f3d-09857774cc2c (Autodesk Fusion 360 design; units mm, degrees)
Autodesk Fusion 360 part; units mm, degrees
sketch "Sketch3" plane through (0, 0, 0) normal (0, 0, 1) x (1, 0, 0)
  line L0 (0, 0) -> (600, 0)
  line L1 (600, 0) -> (600, 975)
  line L2 (0, 1193.3821) -> (0, 0)
  line L3 (0, 1193.3821) -> (600, 975)
  line L4 (600, 0) -> (584, 0)
  line L5 (584, 0) -> (584, 975)
  line L6 (584, 975) -> (600, 975)
  line L7 (600, 975) -> (600, 0)
  line L8 (0, 1187.5586) -> (16, 1187.5586)
  line L9 (16, 1187.5586) -> (16, 1037.5586)
  line L10 (16, 1037.5586) -> (0, 1037.5586)
  line L11 (0, 1037.5586) -> (0, 1187.5586)
  line L12 (0, 500) -> (16, 500)
  line L13 (16, 500) -> (16, 0)
  line L14 (16, 0) -> (0, 0)
  line L15 (0, 0) -> (0, 500)
  line L16 (0, 500) -> (584, 500)
  line L17 (584, 500) -> (584, 516)
  line L18 (584, 516) -> (0, 516)
  line L19 (0, 516) -> (0, 500)
  dimension "d1" = 975
  dimension "d2" = 600
  dimension "d5" = 20
  dimension "d6" = 16
  dimension "d7" = 975
  dimension "d8" = 16
  dimension "d9" = 150
  dimension "d10" = 16
  dimension "d11" = 500
  dimension "d12" = 16
  constraint horizontal L0
  constraint vertical L1
  constraint vertical L2
  constraint coincident L0.start L2.end
  constraint coincident L2.start L3.start
  constraint horizontal L4
  constraint vertical L5
  constraint horizontal L6
  constraint vertical L7
  constraint horizontal L8
  constraint vertical L9
  constraint horizontal L10
  constraint vertical L11
  constraint coincident L2 L8.start
  constraint horizontal L12
  constraint vertical L13
  constraint horizontal L14
  constraint vertical L15
  constraint coincident L2 L12.start
  constraint coincident L3 L8.end
  constraint horizontal L16
  constraint vertical L17
  constraint horizontal L18
  constraint vertical L19
  constraint coincident L5 L17.end
  measures "d1" distance of L0.end L1.end
  measures "d2" distance of L0.start L0.end
  measures "d5" angle of L0 L3
  measures "d6" distance of L5 L7
  measures "d7" distance of L4.end L5.end
  measures "d8" distance of L9 L11
  measures "d9" distance of L8.end L9.end
  measures "d10" distance of L13 L15
  measures "d11" distance of L12.end L13.end
  measures "d12" distance of L16 L18
extrude "Extrude1" add sketch "Sketch3" against normal blind 16 makes body 1 in component "Component'"
extrude "Extrude1'" add sketch "Sketch3" along normal blind 718 separate body contours L2 L8 L9 L10 L11 makes body 2 in component "Component''"
extrude "Extrude1''" add sketch "Sketch3" along normal blind 718 separate body contours L0 L1 L4 L5 L6 L7 L17 makes body 3 in component "Component'''"
extrude "Extrude1'''" add sketch "Sketch3" along normal blind 718 separate body contours L2 L5 L12 L16 L17 L18 L19 makes body 4 in component "Component''''"
extrude "Extrude1''''" add sketch "Sketch3" along normal blind 718 separate body contours L0 L2 L12 L13 L14 L15 L16 makes body 5 in component "Component'''''"
ref_plane "WorkPlane1" through (300, 596.6911, 359) normal (0, 0, 1) x (1, 0, 0)
mirror "Mirror1" about plane through (300, 596.6911, 359) normal (0, 0, 1) of bodies 1 makes body 6 in component "Component'"
ref_plane "WorkPlane2" through (300, 1084.1911, 726) normal (0.34202, 0.939693, 0) x (0.939693, -0.34202, 0)
sketch "Sketch4" plane through (383.5456, 1053.7829, 0) normal (0.34202, 0.939693, 0) x (0.939693, -0.34202, 0)
  line L0 (-408.1607, 0) -> (230.3459, 0) construction
  line L1 (230.3459, 0) -> (230.3459, 16) construction
  line L2 (230.3459, 16) -> (-408.1607, 16) construction
  line L3 (-408.1607, 16) -> (-408.1607, 0) construction
  line L4 (230.3459, 0) -> (215.3109, 0) construction
  line L5 (215.3109, 0) -> (215.3109, -718) construction
  line L6 (215.3109, -718) -> (230.3459, -718) construction
  line L7 (230.3459, -718) -> (230.3459, 0) construction
  line L8 (-391.1339, 0) -> (-406.169, 0) construction
  line L9 (-406.169, 0) -> (-406.169, -718) construction
  line L10 (-406.169, -718) -> (-391.1339, -718) construction
  line L11 (-391.1339, -718) -> (-391.1339, 0) construction
  line L12 (230.3459, -718) -> (-408.1607, -718) construction
  line L13 (-408.1607, -718) -> (-408.1607, -734) construction
  line L14 (-408.1607, -734) -> (230.3459, -734) construction
  line L15 (230.3459, -734) -> (230.3459, -718) construction
  line L16 (-408.1607, 16) -> (230.3459, -734) construction
  line L17 (330.9426, 294.8) -> (-508.7574, 294.8)
  line L18 (-508.7574, 294.8) -> (-508.7574, -1012.8)
  line L19 (-508.7574, -1012.8) -> (330.9426, -1012.8)
  line L20 (330.9426, -1012.8) -> (330.9426, 294.8)
  line L21 (330.9426, 294.8) -> (-508.7574, -1012.8) construction
  line L22 (-508.7574, 294.8) -> (330.9426, -1012.8) construction
  line L23 (-508.7574, 294.8) -> (330.9426, 294.8)
  line L24 (330.9426, 294.8) -> (330.9426, 278.8)
  line L25 (330.9426, 278.8) -> (-508.7574, 278.8)
  line L26 (-508.7574, 278.8) -> (-508.7574, 294.8)
  line L27 (-508.7574, -1012.8) -> (330.9426, -1012.8)
  line L28 (330.9426, -1012.8) -> (330.9426, -996.8)
  line L29 (330.9426, -996.8) -> (-508.7574, -996.8)
  line L30 (-508.7574, -996.8) -> (-508.7574, -1012.8)
  line L31 (-508.7574, 278.8) -> (-492.7574, 278.8)
  line L32 (-492.7574, 278.8) -> (-492.7574, -996.8)
  line L33 (-492.7574, -996.8) -> (-508.7574, -996.8)
  line L34 (-508.7574, -996.8) -> (-508.7574, 278.8)
  line L35 (330.9426, 278.8) -> (314.9426, 278.8)
  line L36 (314.9426, 278.8) -> (314.9426, -996.8)
  line L37 (314.9426, -996.8) -> (330.9426, -996.8)
  line L38 (330.9426, -996.8) -> (330.9426, 278.8)
  line L39 (-88.9074, -359) -> (-88.9074, -996.8) construction
  line L40 (-88.9074, -359) -> (-88.9074, 278.8) construction
  point P0 (-88.9074, -359)
  point P1 (-88.9074, -359)
  point P2 (-88.9074, -511.8)
  point P3 (-88.9074, -206.2)
  dimension "d26" = 839.7
  dimension "d27" = 1307.6
  dimension "d28" = 16
  dimension "d29" = 16
  dimension "d30" = 16
  dimension "d31" = 16
  dimension "d38" = 485
  dimension "d39" = 485
  constraint coincident L2.end L3.start
  constraint coincident L14.end L15.start
  constraint midpoint L16 P1
  constraint horizontal L17
  constraint perpendicular L17 L18
  constraint parallel L17 L19
  constraint parallel L18 L20
  constraint coincident L21 P1
  constraint coincident L22 P1
  constraint coincident P1 P0
  constraint horizontal L23
  constraint vertical L24
  constraint horizontal L25
  constraint vertical L26
  constraint coincident L20 L24.end
  constraint horizontal L27
  constraint vertical L28
  constraint horizontal L29
  constraint vertical L30
  constraint coincident L20 L28.end
  constraint horizontal L31
  constraint vertical L32
  constraint horizontal L33
  constraint vertical L34
  constraint coincident L29 L32.end
  constraint horizontal L35
  constraint vertical L36
  constraint horizontal L37
  constraint vertical L38
  constraint coincident L29 L36.end
  constraint midpoint L29 L39.end
  constraint midpoint L25 L40.end
  constraint coincident L39 P2
  constraint coincident L40 P3
  measures "d26" distance of L17.start L17.end
  measures "d27" distance of L17.end L18.end
  measures "d28" distance of L19 L29
  measures "d29" distance of L17 L25
  measures "d30" distance of L18 L32
  measures "d31" distance of L36 L38
  measures "d38" distance of L29 P2
  measures "d39" distance of L25 P3
extrude "Extrude1'''''" add sketch "Sketch4" along normal blind 104.5 separate body contours L20 L25 L29 L35 L36 L37 L38 | L18 L25 L29 L31 L32 L33 L34 makes body 7 at (-82.6162, 1260.5209, 146.4) makes body 8 at (718.3574, 1006.0592, 571.6) in component "Component''''''"
extrude "Extrude1''''''" add sketch "Sketch4" along normal blind 104.5 separate body contours L17 L18 L20 L23 L24 L25 L26 L31 L35 | L18 L19 L20 L27 L28 L29 L30 L33 L37 makes body 9 at (443.4237, 1069.058, 996.8) makes body 10 at (455.3374, 1101.7906, -278.8) in component "Component'''''''"
extrude "Extrude1'''''''" add sketch "Sketch4" along normal blind 16 separate body contours L25 L29 L32 L36 makes body 11 in component "Component''''''''"
sketch "Sketch5" plane through (389.0179, 1068.818, 0) normal (0.34202, 0.939693, 0) x (0, 0, -1)
  line L0 (278.8, 492.7574) -> (-996.8, 492.7574)
  line L1 (-996.8, 492.7574) -> (-996.8, -314.9426)
  line L2 (-996.8, -314.9426) -> (278.8, -314.9426)
  line L3 (278.8, -314.9426) -> (278.8, 492.7574)
  point P0 (-511.8, 88.9074)
  point P1 (-206.2, 88.9074)
hole "Hole1" at (305.4723, 1099.2262, 511.8) at (305.4723, 1099.2262, 206.2) direction (-0.34202, -0.939693, 0) diameter 100 depth 16 tip angle 180 bodies 11 in component "Component''''''''"
extrude "Extrude1''''''''" add sketch "Sketch4" against normal blind 78.5 from surface at 104.5 separate body contours L25 L29 L32 L36 makes body 12 in component "Component'''''''''"
sketch "Sketch6" plane through (0, 0, 1012.8) normal (0, 0, 1) x (1, 0, 0)
  line L0 (-94.5299, 1227.7882) -> (694.5299, 940.5939)
  line L1 (694.5299, 940.5939) -> (730.2711, 1038.7918)
  line L2 (730.2711, 1038.7918) -> (-58.7888, 1325.9861)
  line L3 (-58.7888, 1325.9861) -> (-94.5299, 1227.7882)
  dimension "d46" = 824.801
  measures "d46" horizontal distance of L0.start L1.end
move_face "Габарит BOE — зазор 2 мм по каждой стороне" offset -2 4 faces at (191.3438, 1179.2533, 996.8) (697.3369, 995.0869, 146.4) (191.3438, 1179.2533, -278.8) (-61.6528, 1271.3365, 146.4) on bodies 12 in component "Component'''''''''"
ref_plane "WorkPlane1" through (0, 0, -88.5) normal (0, 0, 1) x (1, 0, 0) in component "Component''''''''''"
sketch "Sketch1" plane through (0, 0, -88.5) normal (0, 0, 1) x (1, 0, 0) in component "Component''''''''''"
  line L0 (-225, -173.65) -> (-175, -173.65)
  line L1 (-175, -173.65) -> (-175, -157.65)
  line L2 (-175, -157.65) -> (-225, -157.65)
  line L3 (-225, -157.65) -> (-225, -173.65)
extrude "ОП-1 — опирание 10 мм" add sketch "Sketch1" along normal blind 10 separate body makes body 13 in component "Component''''''''''"
sketch "Sketch2" plane through (0, 0, -88.5) normal (0, 0, 1) x (1, 0, 0) in component "Component''''''''''"
  line L0 (175, -173.65) -> (225, -173.65)
  line L1 (225, -173.65) -> (225, -157.65)
  line L2 (225, -157.65) -> (175, -157.65)
  line L3 (175, -157.65) -> (175, -173.65)
extrude "ОП-1 — опирание 10 мм (1)" add sketch "Sketch2" along normal blind 10 separate body makes body 14 in component "Component''''''''''"
sketch "Sketch3 (2)" plane through (0, 0, -88.5) normal (0, 0, 1) x (1, 0, 0) in component "Component''''''''''"
  line L0 (-225, 226.35) -> (-175, 226.35)
  line L1 (-175, 226.35) -> (-175, 242.35)
  line L2 (-175, 242.35) -> (-225, 242.35)
  line L3 (-225, 242.35) -> (-225, 226.35)
extrude "ОП-1 — опирание 10 мм (2)" add sketch "Sketch3 (2)" along normal blind 10 separate body makes body 15 in component "Component''''''''''"
sketch "Sketch4 (2)" plane through (0, 0, -88.5) normal (0, 0, 1) x (1, 0, 0) in component "Component''''''''''"
  line L0 (175, 226.35) -> (225, 226.35)
  line L1 (225, 226.35) -> (225, 242.35)
  line L2 (225, 242.35) -> (175, 242.35)
  line L3 (175, 242.35) -> (175, 226.35)
extrude "ОП-1 — опирание 10 мм (3)" add sketch "Sketch4 (2)" along normal blind 10 separate body makes body 16 in component "Component''''''''''"
sketch "Sketch1 (2)" plane through (0, 0, 0) normal (0, 0, 1) x (1, 0, 0) in component "Component'''''''''''"
  line L0 (653.8, 419.85) -> (-653.8, 419.85)
  line L1 (-653.8, 419.85) -> (-653.8, -419.85)
  line L2 (-653.8, -419.85) -> (653.8, -419.85)
  line L3 (653.8, -419.85) -> (653.8, 419.85)
  line L4 (606, 309.95) -> (-606, 309.95)
  line L5 (-606, 309.95) -> (-606, -372.05)
  line L6 (-606, -372.05) -> (606, -372.05)
  line L7 (606, -372.05) -> (606, 309.95)
  dimension "d67" = 1307.6
  dimension "d68" = 839.7
  dimension "d69" = 1212
  dimension "d70" = 682
  dimension "d73" = 653.8
  dimension "d74" = 419.85
  dimension "d75" = 606
  dimension "d76" = 372.05
  constraint horizontal L0
  constraint vertical L1
  constraint horizontal L2
  constraint vertical L3
  constraint horizontal L4
  constraint vertical L5
  constraint horizontal L6
  constraint vertical L7
  measures "d67" horizontal distance of L1.end L2.end
  measures "d68" vertical distance of L0.start L2.end
  measures "d69" horizontal distance of L5.end L6.end
  measures "d70" vertical distance of L4.start L6.end
  measures "d73" horizontal distance of origin L1.end
  measures "d74" vertical distance of origin L1.end
  measures "d75" horizontal distance of origin L5.end
  measures "d76" vertical distance of origin L5.end
extrude "ПС-1 — полистирол 2 мм" add sketch "Sketch1 (2)" along normal blind 2 separate body makes body 17 in component "Component'''''''''''"
delete_body "RemoveBody1" bodies 12 in component "Component'''''''''"
ref_plane "WorkPlane1" through (0, 0, -24.1) normal (0, 0, 1) x (1, 0, 0) in component "Component''''''''''''"
sketch "Sketch1 (3)" plane through (0, 0, -24.1) normal (0, 0, 1) x (1, 0, 0) in component "Component''''''''''''"
  line L0 (-635.8, -401.85) -> (635.8, -401.85)
  line L1 (635.8, -401.85) -> (635.8, 401.85)
  line L2 (635.8, 401.85) -> (-635.8, 401.85)
  line L3 (-635.8, 401.85) -> (-635.8, -401.85)
extrude "Передняя панель — 24,1 мм (1)" add sketch "Sketch1 (3)" along normal blind 23.1 separate body makes body 18 in component "Component''''''''''''"
ref_plane "WorkPlane2" through (0, 0, -1) normal (0, 0, 1) x (1, 0, 0) in component "Component''''''''''''"
sketch "Sketch2 (2)" plane through (0, 0, -1) normal (0, 0, 1) x (1, 0, 0) in component "Component''''''''''''"
  line L0 (-635.8, -401.85) -> (635.8, -401.85)
  line L1 (635.8, -401.85) -> (635.8, 401.85)
  line L2 (635.8, 401.85) -> (-635.8, 401.85)
  line L3 (-635.8, 401.85) -> (-635.8, -401.85)
  line L4 (-606, -372.05) -> (606, -372.05)
  line L5 (606, -372.05) -> (606, 309.95)
  line L6 (606, 309.95) -> (-606, 309.95)
  line L7 (-606, 309.95) -> (-606, -372.05)
extrude "Передняя рамка — без кнопок (1)" add sketch "Sketch2 (2)" along normal blind 1 bodies 18 in component "Component''''''''''''"
ref_plane "WorkPlane3" through (0, 0, -24.1) normal (0, 0, 1) x (1, 0, 0) in component "Component''''''''''''"
sketch "Sketch3 (3)" plane through (0, 0, -24.1) normal (0, 0, 1) x (1, 0, 0) in component "Component''''''''''''"
  line L0 (-607, -378) -> (607, -378)
  line L1 (607, -378) -> (607, 256)
  line L2 (607, 256) -> (-607, 256)
  line L3 (-607, 256) -> (-607, -378)
extrude "Задний кожух — глубина 43,5 мм (1)" add sketch "Sketch3 (3)" against normal blind 19.4 bodies 18 in component "Component''''''''''''"
ref_plane "WorkPlane4" through (0, 0, -43.5) normal (0, 0, 1) x (1, 0, 0) in component "Component''''''''''''"
sketch "Sketch4 (3)" plane through (0, 0, -43.5) normal (0, 0, 1) x (1, 0, 0) in component "Component''''''''''''"
  line L0 (-548, -119) -> (548, -119)
  line L1 (548, -119) -> (548, 258)
  line L2 (548, 258) -> (225, 258)
  line L3 (225, 258) -> (225, 310)
  line L4 (225, 310) -> (-185, 310)
  line L5 (-185, 310) -> (-185, 258)
  line L6 (-185, 258) -> (-548, 258)
  line L7 (-548, 258) -> (-548, -119)
extrude "Нижний выступ корпуса — глубина 78,5 мм (1)" add sketch "Sketch4 (3)" against normal blind 35 bodies 18 in component "Component''''''''''''"
ref_plane "WorkPlane5" through (0, 0, -43.5) normal (0, 0, 1) x (1, 0, 0) in component "Component''''''''''''"
sketch "Sketch5 (2)" plane through (0, 0, -43.5) normal (0, 0, 1) x (1, 0, 0) in component "Component''''''''''''"
  line L0 (-230, -182) -> (-170, -182)
  line L1 (-170, -182) -> (-170, -145)
  line L2 (-170, -145) -> (-230, -145)
  line L3 (-230, -145) -> (-230, -182)
extrude "Верхний выступ задника -200 (1)" add sketch "Sketch5 (2)" against normal blind 35 bodies 18 in component "Component''''''''''''"
ref_plane "WorkPlane6" through (0, 0, -43.5) normal (0, 0, 1) x (1, 0, 0) in component "Component''''''''''''"
sketch "Sketch6 (2)" plane through (0, 0, -43.5) normal (0, 0, 1) x (1, 0, 0) in component "Component''''''''''''"
  line L0 (170, -182) -> (230, -182)
  line L1 (230, -182) -> (230, -145)
  line L2 (230, -145) -> (170, -145)
  line L3 (170, -145) -> (170, -182)
extrude "Верхний выступ задника 200 (1)" add sketch "Sketch6 (2)" against normal blind 35 bodies 18 in component "Component''''''''''''"
ref_plane "WorkPlane7" through (0, 0, -1) normal (0, 0, 1) x (1, 0, 0) in component "Component''''''''''''"
sketch "Sketch7" plane through (0, 0, -1) normal (0, 0, 1) x (1, 0, 0) in component "Component''''''''''''"
  line L0 (-606, -372.05) -> (606, -372.05)
  line L1 (606, -372.05) -> (606, 309.95)
  line L2 (606, 309.95) -> (-606, 309.95)
  line L3 (-606, 309.95) -> (-606, -372.05)
extrude "Плоскость дисплея (1)" add sketch "Sketch7" along normal blind 1 separate body makes body 19 in component "Component''''''''''''"
component "Component'" placed x (1, 0, 0) y (0, 1, 0) z (0, 0, 1) at (0, 0, 0)
component "Component''" placed x (1, 0, 0) y (0, 1, 0) z (0, 0, 1) at (0, 0, 0)
component "Component'''" placed x (1, 0, 0) y (0, 1, 0) z (0, 0, 1) at (0, 0, 0)
component "Component''''" placed x (1, 0, 0) y (0, 1, 0) z (0, 0, 1) at (0, 0, 0)
component "Component'''''" placed x (1, 0, 0) y (0, 1, 0) z (0, 0, 1) at (0, 0, 0)
component "Component''''''" placed x (1, 0, 0) y (0, 1, 0) z (0, 0, 1) at (0, 0, 0)
component "Component'''''''" placed x (1, 0, 0) y (0, 1, 0) z (0, 0, 1) at (0, 0, 0)
component "Component''''''''" placed x (1, 0, 0) y (0, 1, 0) z (0, 0, 1) at (0, 0, 0)
component "Component'''''''''" placed x (1, 0, 0) y (0, 1, 0) z (0, 0, 1) at (0, 0, 0)
component "Component''''''''''" placed x (0, 0, 1) y (0.939693, -0.34202, 0) z (0.34202, 0.939693, 0) at (335.7411, 1182.3889, 359)
component "Component'''''''''''" placed x (0, 0, 1) y (0.939693, -0.34202, 0) z (0.34202, 0.939693, 0) at (335.7411, 1182.3889, 359)
component "Component''''''''''''" placed x (0, 0, 1) y (0.939693, -0.34202, 0) z (0.34202, 0.939693, 0) at (335.7411, 1182.3889, 359) in component "Component'''''''''"
equation "d26 = ScreenHeight + 2 * ScreenSideGap + 32 mm"
equation "d27 = ScreenWidth + 2 * ScreenSideGap + 32 mm"
equation "d32 = ScreenTrayDepth"
equation "d34 = ScreenTrayDepth"
equation "d43 = ScreenTrayDepth"
equation "d44 = -ScreenDepth"
equation "ScreenWidth = 1271.6 mm" comment "Ширина корпуса BOE P55BA-BAR по PDF"
equation "ScreenHeight = 803.7 mm" comment "Высота корпуса BOE P55BA-BAR по PDF"
equation "ScreenDepth = 78.5 mm" comment "Полная глубина BOE P55BA-BAR по PDF"
equation "ScreenSideGap = 2 mm" comment "Монтажный зазор по каждой стороне"
equation "ScreenTrayDepth = ScreenDepth + 10 mm + 16 mm" comment "Глубина короба; задник 16 мм, свободно 40.5 мм за экраном"
equation "d52 = -ScreenSideGap"
equation "d53 = 16 mm - ScreenTrayDepth"
equation "d55 = ScreenTrayDepth - ScreenDepth - 16 mm"
equation "d57 = ScreenTrayDepth - ScreenDepth - 16 mm"
equation "d59 = ScreenTrayDepth - ScreenDepth - 16 mm"
equation "d61 = ScreenTrayDepth - ScreenDepth - 16 mm"
equation "CoverThickness = 2 mm" comment "Полистирол по указанию пользователя"
equation "ViewWidth = 1212 mm" comment "Окно по размерному чертежу PDF, таблица противоречит чертежу"
equation "ViewHeight = 682 mm" comment "Окно по размерному чертежу PDF"
equation "ViewTopInset = ( ScreenWidth - ViewWidth ) / 2" comment "Предложенная привязка окна: верхний отступ равен боковому, проверить по ИК-рамке"
equation "d67 = ScreenWidth + 2 * ScreenSideGap + 32 mm"
equation "d68 = ScreenHeight + 2 * ScreenSideGap + 32 mm"
equation "d69 = ViewWidth"
equation "d70 = ViewHeight"
equation "d71 = CoverThickness"
equation "d73 = ( ScreenWidth + 2 * ScreenSideGap + 32 mm ) / 2"
equation "d74 = ( ScreenHeight + 2 * ScreenSideGap + 32 mm ) / 2"
equation "d75 = ViewWidth / 2"
equation "d76 = ScreenHeight / 2 - ViewTopInset"
named bodies: "ЛДСП-1 — деталь 1", "ЛДСП-2 — деталь 1", "ЛДСП-3 — деталь 1", "ЛДСП-4 — деталь 1", "ЛДСП-5 — деталь 1", "ЛДСП-1 — деталь 2", "ЛДСП-6 — деталь 1", "ЛДСП-6 — деталь 2", "ЛДСП-7 — деталь 1", "ЛДСП-7 — деталь 2", "ЛДСП-8 — деталь 1", "Габарит экрана BOE P55BA-BAR — 35 кг", "ОП-1 — вкладыш 1", "ОП-1 — вкладыш 2", "ОП-1 — вкладыш 3", "ОП-1 — вкладыш 4", "ПС-1 — накладка с окном 1212х682 мм", "BOE — корпус с задними выступами", "BOE — экран без элементов управления"
